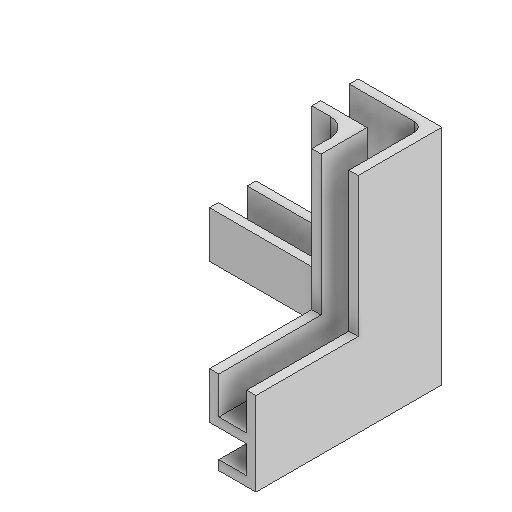
# Autodesk Inventor part: esquinera tope IZQ
Saved by Autodesk Inventor 2025.2 (Build 292293000, 293)
## iProperties
Created: 2026-09-20
Part Number: esquinera tope IZQ
Material: Genérico
Document SubType Name: Modeling
Designer: autor
Density: 1 g/cm^3
Appearance: Valor por defecto
Author: autor
Autodesk Inventor part; units mm, degrees
ref_plane "YZ Plane" through (0, 0, 0) normal (1, 0, 0) x (0, 1, 0)
ref_plane "XZ Plane" through (0, 0, 0) normal (0, 1, 0) x (-1, 0, 0)
ref_plane "XY Plane" through (0, 0, 0) normal (0, 0, 1) x (1, 0, 0)
sketch "Boceto1" plane through (0, 0, 0) normal (0, 0, 1) x (1, 0, 0)
  line L0 (-17.4419, 1.5632) -> (2.5581, 1.5632)
  line L1 (2.5581, 1.5632) -> (2.5581, 21.5632)
  line L2 (2.5581, 21.5632) -> (-2.4419, 21.5632)
  line L3 (-2.4419, 21.5632) -> (-2.4419, 6.5632)
  line L4 (-2.4419, 6.5632) -> (-17.4419, 6.5632)
  line L5 (-17.4419, 6.5632) -> (-17.4419, 1.5632)
  point P0 (0, 0)
  dimension "d0" = 20
  dimension "d1" = 20
  dimension "d2" = 5
  dimension "d3" = 15
  constraints: 12 end point, 5 perpendicular, 1 horizontal
  measures "d0" distance of L0.start L0.end
  measures "d1" distance of L0.end L1.end
  measures "d2" distance of L1.end L2.end
  measures "d3" distance of L2.end L3.end
extrude "Extrusión1" add sketch "Boceto1" along normal blind 5
sketch "Boceto3" plane through (2.5581, 1.5632, 0) normal (1, 0, 0) x (0, 0, -1)
  line L0 (-5, 0) -> (-5, 20) projected
  line L1 (-5, 0) -> (-20, 0)
  line L2 (-20, 0) -> (-20, 5)
  line L3 (-20, 5) -> (-5, 5)
  point P0 (0, -1.5632)
  dimension "d6" = 15
  dimension "d7" = 5
  constraints: 6 end point, 2 perpendicular, 1 horizontal, 1 point on line
  measures "d6" distance of L0.start L1.end
  measures "d7" distance of L1.end L2.end
extrude "Extrusión2" add sketch "Boceto3" against normal blind 5
sketch "Boceto4" plane through (2.5581, 1.5632, 20) normal (0, 0, 1) x (1, 0, 0)
  line L0 (0, 20) -> (-5, 20) projected
  line L1 (-4, 20) -> (-1, 20)
  line L2 (-1, 20) -> (-1, 1)
  line L3 (-1, 1) -> (-4, 1)
  line L4 (-4, 1) -> (-4, 20)
  line L5 (-5, 20) -> (-5, 5) projected
  point P0 (-2.5581, -1.5632)
  dimension "d10" = 3
  dimension "d11" = 19
  dimension "d12" = 1
  constraints: 8 end point, 2 parallel, 1 horizontal, 1 perpendicular, 1 point on line
  measures "d10" distance of L2.end L3.end
  measures "d11" distance of L1.end L2.end
  measures "d12" distance between parallel lines of L5 L4
extrude "Extrusión3" cut sketch "Boceto4" against normal blind 19
sketch "Boceto5" plane through (-17.4419, 1.5632, 0) normal (-1, 0, 0) x (0, 0, 1)
  line L0 (0, 20) -> (5, 20) projected
  line L1 (0.95, 20) -> (4.05, 20)
  line L2 (4.05, 20) -> (4.05, 1)
  line L3 (4.05, 1) -> (0.95, 1)
  line L4 (0.95, 1) -> (0.95, 20)
  line L5 (0, 20) -> (0, 5) projected
  point P0 (0, -1.5632)
  dimension "d15" = 3.1
  dimension "d16" = 19
  dimension "d38" = 0.95
  constraints: 8 end point, 2 parallel, 1 horizontal, 1 perpendicular, 1 point on line
  measures "d15" distance of L2.end L3.end
  measures "d16" distance of L1.end L2.end
  measures "d38" distance between parallel lines of L5 L4
extrude "Extrusión4" cut sketch "Boceto5" against normal blind 19
sketch "Boceto6" plane through (-2.4419, 21.5632, 5) normal (0, 1, 0) x (1, 0, 0)
  line L0 (1, 0.95) -> (0, 0.95) projected
  line L1 (0, 0.95) -> (0, 0) projected
  line L2 (1, 0) -> (0, 0) projected
  line L3 (1, 0) -> (1, 0.95) projected
  point P0 (2.4419, 5)
extrude "Extrusión5" cut sketch "Boceto6" against normal up to surface (15 mm away)
sketch "Boceto7" plane through (-17.4419, 1.5632, 0) normal (-1, 0, 0) x (0, 0, 1)
  line L0 (0, 0) -> (0, -4)
  line L1 (0, -4) -> (5, -4)
  line L2 (5, -4) -> (5, -3)
  line L3 (5, -3) -> (1, -3)
  line L4 (1, -3) -> (1, 0)
  line L5 (0, 0) -> (20, 0) projected
  line L6 (0, 0) -> (1, 0)
  point P0 (0, -1.5632)
  dimension "d22" = 4
  dimension "d23" = 5
  dimension "d24" = 1
  dimension "d25" = 4
  constraints: 12 end point, 5 perpendicular, 1 point on line, 1 vertical
  measures "d22" distance of L0.start L0.end
  measures "d23" distance of L0.end L1.end
  measures "d24" distance of L1.end L2.end
  measures "d25" distance of L2.end L3.end
extrude "Extrusión6" add sketch "Boceto7" against normal up to surface (20 mm away)
sketch "Boceto8" plane through (2.5581, 21.5632, 5) normal (1, 0, 0) x (0, 0, -1)
  line L0 (5, -24) -> (5, 0) projected
  line L1 (5, -24) -> (0, -24)
  line L2 (0, -24) -> (0, -20)
  line L3 (0, -20) -> (5, -20)
  line L4 (5, -20) -> (5, -24)
  point P0 (5, -21.5632)
  constraints: 8 end point, 2 parallel, 1 horizontal, 1 perpendicular
extrude "Extrusión7" add sketch "Boceto8" against normal blind 1
sketch "Boceto10" plane through (2.5581, 1.5632, 20) normal (0, 0, 1) x (1, 0, 0)
  line L0 (0, -4) -> (0, 20) projected
  line L1 (0, 0) -> (0, -4)
  line L2 (0, -4) -> (-4, -4)
  line L3 (-4, -4) -> (-4, -2.9747)
  line L4 (-4, -2.9747) -> (-0.9758, -2.9747)
  line L5 (-0.9758, -2.9747) -> (-0.9758, 0)
  line L6 (-0.9758, 0) -> (0, 0)
  point P0 (-2.5581, -1.5632)
  dimension "d30" = 4
  constraints: 12 end point, 5 perpendicular, 1 vertical
  measures "d30" distance of L0.start L2.end
extrude "Extrusión8" add sketch "Boceto10" against normal up to surface (15 mm away)
sketch "Boceto13" plane through (-2.4419, 6.5632, 0) normal (-1, 0, 0) x (0, 0, 1)
  line L0 (0.95, 0) -> (0.95, 15) projected
  line L1 (0, 15) -> (0.95, 15) projected
  line L2 (0, 15) -> (0, 0) projected
  line L3 (0, 0) -> (0.95, 0) projected
  point P0 (0, -6.5632)
extrude "Extrusión11" add sketch "Boceto13" along normal blind 4
sketch "Boceto14" plane through (0, 0, 5) normal (0, 0, 1) x (1, 0, 0)
  line L0 (1.5581, 21.5632) -> (1.5581, 6.5632) projected
  line L1 (1.5581, 6.5632) -> (2.5581, 6.5632) projected
  line L2 (2.5581, 6.5632) -> (2.5581, 21.5632) projected
  line L3 (2.5581, 21.5632) -> (1.5581, 21.5632) projected
  point P0 (0, 0)
extrude "Extrusión12" add sketch "Boceto14" along normal blind 4
sketch "Boceto15" plane through (0, 0, 5) normal (0, 0, 1) x (1, 0, 0)
  line L0 (-1.4419, 2.5632) -> (-1.4419, 6.5632) projected
  line L1 (-6.4419, 21.5632) -> (-1.4419, 21.5632)
  line L2 (-1.4419, 21.5632) -> (-1.4419, 6.5632)
  line L3 (-1.4419, 6.5632) -> (-6.4419, 6.5632)
  line L4 (-6.4419, 6.5632) -> (-6.4419, 21.5632)
  point P0 (0, 0)
  constraints: 8 end point, 2 parallel, 1 horizontal, 1 perpendicular
extrude "Extrusión13" add sketch "Boceto15" against normal up to surface (0.95 mm away)
sketch "Boceto16" plane through (-2.4419, 1.5632, 0) normal (-1, 0, 0) x (0, 0, 1)
  line L0 (4.05, 5) -> (4.05, 20) projected
  line L1 (9, 20) -> (4.05, 20)
  line L2 (4.05, 20) -> (4.05, 5)
  line L3 (4.05, 5) -> (9, 5)
  line L4 (9, 5) -> (9, 20)
  point P0 (0, -1.5632)
  constraints: 8 end point, 2 parallel, 1 horizontal, 1 perpendicular
extrude "Extrusión14" add sketch "Boceto16" against normal up to surface (1 mm away)
fillet "Empalme2" radius 2 1 edges at (-2.4419, 11.5632, 5)
fillet "Empalme3" radius 1 1 edges at (1.5581, 12.0632, 0.95)
sketch "Boceto17" plane through (-17.4419, 1.5632, 5) normal (-1, 0, 0) x (0, 0, 1)
  line L0 (-5, -4) -> (0, -4) projected
  line L1 (0, -3) -> (-4, -3) projected
  line L2 (-4, -3) -> (-4, 0) projected
  line L3 (0, -4) -> (0, -3) projected
  line L4 (-4, 0) -> (-5, 0)
  line L5 (-5, -4) -> (-5, 20) projected
  point P0 (-5, -1.5632)
  constraints: 2 end point, 1 horizontal, 1 point on line
extrude "Extrusión15" cut sketch "Boceto17" against normal up to surface (19.0242 mm away)
